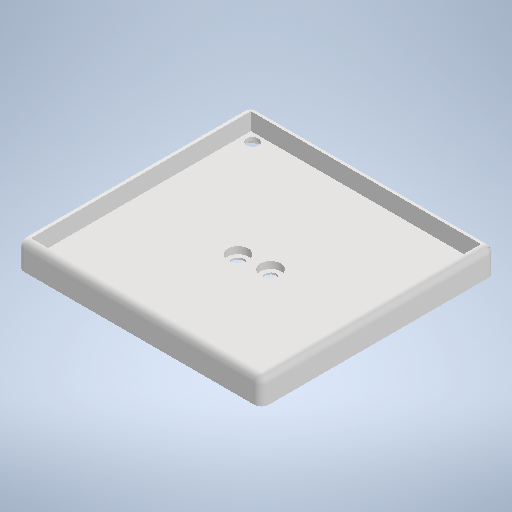
# Autodesk Inventor part: socle
Saved by Autodesk Inventor 2025.2 (Build 292293000, 293)
## iProperties
Created: 2026-08-28
Part Number: socle
Material: Générique
Document SubType Name: Modeling
Designer: mattéo
Density: 1 g/cm^3
Appearance: Par défaut
Author: mattéo
Autodesk Inventor part; units mm, degrees
ref_plane "YZ Plane" through (0, 0, 0) normal (1, 0, 0) x (0, 1, 0)
ref_plane "XZ Plane" through (0, 0, 0) normal (0, 1, 0) x (-1, 0, 0)
ref_plane "XY Plane" through (0, 0, 0) normal (0, 0, 1) x (1, 0, 0)
sketch "Esquisse1" plane through (0, 0, 0) normal (0, 1, 0) x (-1, 0, 0)
  line L0 (-33.5, 32) -> (33.5, 32)
  line L1 (33.5, 32) -> (33.5, -32)
  line L2 (33.5, -32) -> (-33.5, -32)
  line L3 (-33.5, -32) -> (-33.5, 32)
  line L4 (-33.5, 32) -> (33.5, -32) construction
  line L5 (33.5, 32) -> (-33.5, -32) construction
  line L6 (-35.5938, 34) -> (35.5937, 34)
  line L7 (35.5937, 34) -> (35.5937, -34)
  line L8 (35.5937, -34) -> (-35.5938, -34)
  line L9 (-35.5938, -34) -> (-35.5938, 34)
  line L10 (-35.5938, 34) -> (35.5937, -34) construction
  line L11 (35.5937, 34) -> (-35.5938, -34) construction
  point P0 (0, 0)
  dimension "d0" = 67
  dimension "d1" = 64
  dimension "d2" = 2
  constraints: 24 end point, 4 midpoint, 4 parallel, 2 horizontal, 2 perpendicular, 1 point on line
  measures "d0" distance of L1.end L2.end
  measures "d1" distance of L0.end L1.end
  measures "d2" distance between parallel lines of L8 L2
extrude "Extrusion1" add sketch "Esquisse1" along normal blind 2.5 contours L0 L1 L2 L3 | L6 L7 L8 L9
sketch "Esquisse2" plane through (0, 2.5, 0) normal (0, 1, 0) x (1, 0, 0)
  line L0 (-33.5, -32) -> (-33.5, 32) projected
  line L1 (-35.5937, -34) -> (-35.5937, 34) projected
  line L2 (-33.5, 32) -> (33.5, 32) projected
  line L3 (-35.5937, 34) -> (35.5938, 34) projected
  line L4 (33.5, 32) -> (33.5, -32) projected
  line L5 (35.5938, -34) -> (35.5938, 34) projected
  line L6 (33.5, -32) -> (-33.5, -32) projected
  line L7 (-35.5937, -34) -> (35.5938, -34) projected
  point P0 (0, 0)
extrude "Extrusion2" add sketch "Esquisse2" along normal blind 5
sketch "Esquisse3" plane through (0, 2.5, 0) normal (0, 1, 0) x (1, 0, 0)
  line L0 (30.5, -29.5) -> (-30.5, -29.5) construction
  line L1 (-30.5, -29.5) -> (-30.5, 29.5) construction
  line L2 (-30.5, 29.5) -> (30.5, 29.5) construction
  line L3 (30.5, 29.5) -> (30.5, -29.5) construction
  line L4 (30.5, -29.5) -> (-30.5, 29.5) construction
  line L5 (-30.5, -29.5) -> (30.5, 29.5) construction
  circle A0 centre (-30.5, 29.5) radius 1.75
  circle A1 centre (30.5, 29.5) radius 1.75
  circle A2 centre (30.5, -29.5) radius 1.75
  circle A3 centre (-30.5, -29.5) radius 1.75
  circle A4 centre (-4.25, -1) radius 1.75
  circle A5 centre (4.25, 0) radius 1.75
  line L6 (4.25, 0) -> (-4.25, 0) construction
  point P0 (0, 0)
  dimension "d7" = 61
  dimension "d8" = 59
  dimension "d9" = 3.5
  dimension "d12" = 8.5
  dimension "d13" = 1
  dimension "d14" = 3.5
  constraints: 14 end point, 6 centre point, 4 coincident, 4 equal radius, 3 midpoint, 2 horizontal, 2 parallel, 1 perpendicular, 1 vertical alignment
  measures "d7" distance of L1.end L2.end
  measures "d8" distance of L0.end L1.end
  measures "d9" diameter of A0
  measures "d12" horizontal distance of L6.start A4.centre
  measures "d13" distance of L6.end A4.centre
  measures "d14" diameter of A5
extrude "Extrusion3" cut sketch "Esquisse3" against normal through all
sketch "Esquisse4" plane through (0, 0, 0) normal (0, -1, 0) x (1, 0, 0)
  circle A0 centre (-30.5, 29.5) radius 1.75 projected
  circle A1 centre (-30.5, -29.5) radius 1.75 projected
  circle A2 centre (4.25, 0) radius 1.75 projected
  circle A3 centre (30.5, 29.5) radius 1.75 projected
  circle A4 centre (30.5, -29.5) radius 1.75 projected
  circle A5 centre (-4.25, 1) radius 1.75 projected
  line L0 (35.5938, -34) -> (-35.5937, -34) projected
  line L1 (35.5938, 34) -> (35.5938, -34) projected
  line L2 (-35.5937, 34) -> (35.5938, 34) projected
  line L3 (-35.5937, -34) -> (-35.5937, 34) projected
  line L4 (-27.5, 27.7679) -> (-30.5, 26.0359)
  line L5 (-30.5, 26.0359) -> (-33.5, 27.7679)
  line L6 (-33.5, 27.7679) -> (-33.5, 31.2321)
  line L7 (-33.5, 31.2321) -> (-30.5, 32.9641)
  line L8 (-30.5, 32.9641) -> (-27.5, 31.2321)
  line L9 (-27.5, 31.2321) -> (-27.5, 27.7679)
  line L10 (27.5, 27.7679) -> (27.5, 31.2321)
  line L11 (27.5, 31.2321) -> (30.5, 32.9641)
  line L12 (30.5, 32.9641) -> (33.5, 31.2321)
  line L13 (33.5, 31.2321) -> (33.5, 27.7679)
  line L14 (33.5, 27.7679) -> (30.5, 26.0359)
  line L15 (30.5, 26.0359) -> (27.5, 27.7679)
  line L16 (27.5, -31.2321) -> (27.5, -27.7679)
  line L17 (27.5, -27.7679) -> (30.5, -26.0359)
  line L18 (30.5, -26.0359) -> (33.5, -27.7679)
  line L19 (33.5, -27.7679) -> (33.5, -31.2321)
  line L20 (33.5, -31.2321) -> (30.5, -32.9641)
  line L21 (30.5, -32.9641) -> (27.5, -31.2321)
  line L22 (-27.5, -31.2321) -> (-30.5, -32.9641)
  line L23 (-30.5, -32.9641) -> (-33.5, -31.2321)
  line L24 (-33.5, -31.2321) -> (-33.5, -27.7679)
  line L25 (-33.5, -27.7679) -> (-30.5, -26.0359)
  line L26 (-30.5, -26.0359) -> (-27.5, -27.7679)
  line L27 (-27.5, -27.7679) -> (-27.5, -31.2321)
  point P0 (0, 0)
  dimension "d15" = 6
  dimension "d16" = 6
  dimension "d17" = 6
  dimension "d18" = 6
  constraints: 48 end point, 4 coincident, 4 vertical, 52 other
  measures "d15" distance between parallel lines of L9 L6
  measures "d16" distance between parallel lines of L27 L24
  measures "d17" distance between parallel lines of L19 L16
  measures "d18" distance between parallel lines of L13 L10
extrude "Extrusion4" cut sketch "Esquisse4" against normal blind 1.5 contours L4 L5 L6 L7 L8 L9 | L10 L11 L12 L13 L14 L15 | L16 L17 L18 L19 L20 L21 | L22 L23 L24 L25 L26 L27
fillet "Congé1" radius 2 8 edges at (-35.5937, 3.75, 34) (35.5938, 3.75, 34) (35.5938, 3.75, -34) (-35.5937, 3.75, -34) (35.5938, 7.5, 0) (0, 7.5, 34) (0, 7.5, -34) (-35.5937, 7.5, 0)
sketch "Esquisse5" plane through (0, 2.5, 0) normal (0, 1, 0) x (1, 0, 0)
  circle A0 centre (-4.25, -1) radius 1.75 projected
  circle A1 centre (4.25, 0) radius 1.75 projected
  circle A2 centre (-4.25, -1) radius 3
  circle A3 centre (4.25, 0) radius 3
  point P0 (0, 0)
  dimension "d22" = 6
  constraints: 2 centre point, 2 coincident, 1 equal radius
  measures "d22" diameter of A2
extrude "Extrusion5" cut sketch "Esquisse5" against normal blind 2
equation "\"d16\" = d15"
equation "\"d17\" = d16"
equation "\"d18\" = d15"
